WireContainer (Autodesk Fusion 360 design; units mm, degrees)
Autodesk Fusion 360 part; units mm, degrees
sketch "Sketch1" plane through (0, 0, 0) normal (0, 1, 0) x (1, 0, 0)
  line L0 (-10, 0) -> (-9.4967, 0)
  line L1 (-11.25, 3.25) -> (11.25, 3.25)
  line L2 (-11.25, 3.25) -> (11.25, 3.25)
  line L3 (11.25, 3.25) -> (11.25, 8)
  line L4 (11.25, 8) -> (-11.25, 8)
  line L5 (-11.25, 8) -> (-11.25, 3.25)
  line L6 (0.0172, 7.9572) -> (0.0172, 2.9572)
  circle A0 centre (0.0172, 2.9572) radius 5
  line L7 (0.0172, 2.9572) -> (-4.9828, 2.9572)
  line L8 (0.0172, 2.9572) -> (5.0172, 2.9572)
  circle A1 centre (0.0172, 2.9572) radius 5.75
  line L9 (5.0172, 2.9572) -> (5.0172, 8)
  line L10 (-4.9828, 2.9572) -> (-4.9828, 8)
  line L11 (-11.25, 3.25) -> (-13.75, 3.25)
  line L12 (-13.75, 3.25) -> (-13.75, 8)
  line L13 (-13.75, 8) -> (-11.25, 8)
  line L14 (-11.25, 8) -> (-11.25, 3.25)
  line L15 (11.25, 3.25) -> (13.75, 3.25)
  line L16 (13.75, 3.25) -> (13.75, 8)
  line L17 (13.75, 8) -> (11.25, 8)
  line L18 (11.25, 8) -> (11.25, 3.25)
  dimension "d6" = 4.75
  dimension "d9" = 10
  dimension "d10" = 11.5
  dimension "d23" = 5
  dimension "d24" = 22.5
  dimension "d25" = 2.5
  dimension "d26" = 2.5
  constraint vertical L3
  constraint vertical L5
  constraint coincident L6.end A0.centre
  constraint coincident A0 L7.end
  constraint perpendicular L6 L7
  constraint coincident A0 L8.end
  constraint concentric A0 A1
  constraint coincident L4 L9.end
  constraint perpendicular L4 L9
  constraint coincident L4 L10.end
  constraint tangent A0 L10
  constraint perpendicular L4 L10
  constraint horizontal L11
  constraint vertical L12
  constraint horizontal L13
  constraint vertical L14
  constraint horizontal L15
  constraint vertical L16
  constraint horizontal L17
  constraint vertical L18
  measures "d6" distance of L1.start L4.end
  measures "d9" diameter of A0
  measures "d10" diameter of A1
  measures "d23" distance of L6.start L6.end
  measures "d24" distance of L3.end L4.end
  measures "d25" distance of L1.start L11.end
  measures "d26" distance of L1.end L15.end
extrude "Extrude4" add sketch "Sketch1" along normal blind 20 contours L1 L2 L4 L5 A1 L10 L14 | L5 L11 L12 L13 L14 | L1 L2 A1 L10 | L1 L2 A0 A1 L9 L10 | L1 L2 L3 L4 A1 L9 L18 | L1 L2 A1 L9 | L3 L15 L16 L17 L18
sketch "Sketch3" plane through (0, 0, -3.25) normal (0, 0, 1) x (1, 0, 0)
  line L0 (-13.75, 0) -> (-5.7253, 0)
  line L1 (-5.7253, 0) -> (-5.7253, 20)
  line L2 (-5.7253, 20) -> (-13.75, 20)
  line L3 (-13.75, 20) -> (-13.75, 0)
  line L4 (-9.7377, 20) -> (-9.7377, 10)
  circle A0 centre (-9.7377, 10) radius 2.5
  dimension "d29" = 10
  dimension "d30" = 5
  constraint midpoint L2 L4.start
  constraint coincident L4.end A0.centre
  measures "d29" distance of L4.start L4.end
  measures "d30" diameter of A0
extrude "Extrude5" cut sketch "Sketch3" against normal up to surface (4.75 mm away) contours A0
sketch "Sketch4" plane through (0, 0, -3.25) normal (0, 0, 1) x (1, 0, 0)
  line L0 (5.7598, 0) -> (13.75, 0)
  line L1 (13.75, 0) -> (13.75, 20)
  line L2 (13.75, 20) -> (5.7598, 20)
  line L3 (5.7598, 20) -> (5.7598, 0)
  line L4 (9.7549, 20) -> (9.7549, 10)
  circle A0 centre (9.7549, 10) radius 2.5
  dimension "d33" = 10
  dimension "d34" = 5
  constraint midpoint L2 L4.start
  constraint coincident L4.end A0.centre
  measures "d33" distance of L4.start L4.end
  measures "d34" diameter of A0
extrude "Extrude6" cut sketch "Sketch4" against normal up to surface (4.75 mm away) contours A0
chamfer "Chamfer2" distance 0.5 angle 45 3 edges at (5.0172, 20, -5.4786) (0.0172, 20, 2.0428) (-4.9828, 20, -5.4786) tangent chain off
fillet "Fillet2" radius 0.3 6 edges at (-5.4828, 20, -5.4786) (0.0172, 20, 2.5428) (5.5172, 20, -5.4786) (5.0172, 19.5, -5.4786) (0.0172, 19.5, 2.0428) (-4.9828, 19.5, -5.4786)
named bodies: "2020 90 degree wire retainer"
